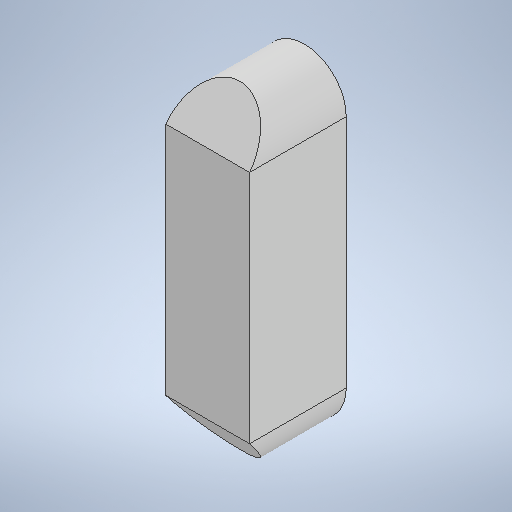
# Autodesk Inventor part: Camara
Saved by Autodesk Inventor 2025.3 (Build 293356000, 356)
## iProperties
Created: 2026-11-27
Part Number: Camara
Material: Genérico
Document SubType Name: Modeling
Designer: STEVEN LONDOÑO
Density: 1 g/cm^3
Appearance: Valor por defecto
Author: STEVEN LONDOÑO
Autodesk Inventor part; units mm, degrees
ref_plane "YZ Plane" through (0, 0, 0) normal (1, 0, 0) x (0, 1, 0)
ref_plane "XZ Plane" through (0, 0, 0) normal (0, 1, 0) x (-1, 0, 0)
ref_plane "XY Plane" through (0, 0, 0) normal (0, 0, 1) x (1, 0, 0)
sketch "Boceto1" plane through (0, 0, 0) normal (0, 0, 1) x (1, 0, 0)
  line L0 (18.2421, 79.1788) -> (18.2421, 6.2088)
  line L1 (-7.7879, 6.2088) -> (-7.7879, 79.1788)
  arc A0 (18.2421, 79.1788) -> (-7.7879, 79.1788) centre (5.2271, 79.1788) ccw
  arc A1 (-7.7879, 6.2088) -> (18.2421, 6.2088) centre (5.2271, 6.2088) ccw
  point P0 (0, 0)
  dimension "d2" = 26.03
  dimension "d3" = 26.03
  constraints: 4 end point, 4 point on circle, 2 centre point, 1 parallel
  measures "d2" diameter of A0
  measures "d3" diameter of A1
extrude "Extrusión1" add sketch "Boceto1" along normal blind 30
sketch "Boceto2" plane through (18.2421, 6.2088, 0) normal (1, 0, 0) x (0, 0, -1)
  line L0 (0, 0) -> (0, -13.015) projected
  line L1 (0, -13.015) -> (-20, -13.015)
  line L2 (0, -13.015) -> (-30, -13.015) projected
  line L3 (-30, 0) -> (-30, 72.97) projected
  line L4 (-20, -13.015) -> (-30, 0)
  line L5 (-30, 0) -> (-30, -13.015) projected
  line L6 (-30, -13.015) -> (-30, 0)
  line L7 (-30, 85.985) -> (-30, 72.97) projected
  line L8 (-30, 85.985) -> (-30, 72.97)
  line L9 (-30, 72.97) -> (-20, 85.985)
  line L10 (0, 85.985) -> (-30, 85.985) projected
  line L11 (-20, -13.015) -> (-30, -13.015)
  line L12 (-30, 0) -> (-30, -13.015)
  line L13 (-20, 85.985) -> (-30, 85.985)
  point P0 (0, -6.2088)
  dimension "d6" = 20
  dimension "d7" = 13.015
  constraints: 16 end point, 4 collinear, 2 point on line, 1 vertical
  measures "d6" distance of L0.end L1.end
  measures "d7" distance of L7.start L3.end
extrude "Extrusión2" cut sketch "Boceto2" against normal blind 30
sketch "Boceto3" plane through (0, 0, 0) normal (0, 0, -1) x (-1, 0, 0)
  circle A0 centre (-5.2271, 42.6938) radius 6.5
  circle A1 centre (-5.2271, 42.6938) radius 1.5
  point P0 (0, 0)
  dimension "d10" = 13
  dimension "d11" = 3
  constraints: 2 centre point, 1 coincident
  measures "d10" diameter of A0
  measures "d11" diameter of A1
extrude "Extrusión3" cut sketch "Boceto3" against normal blind 5
